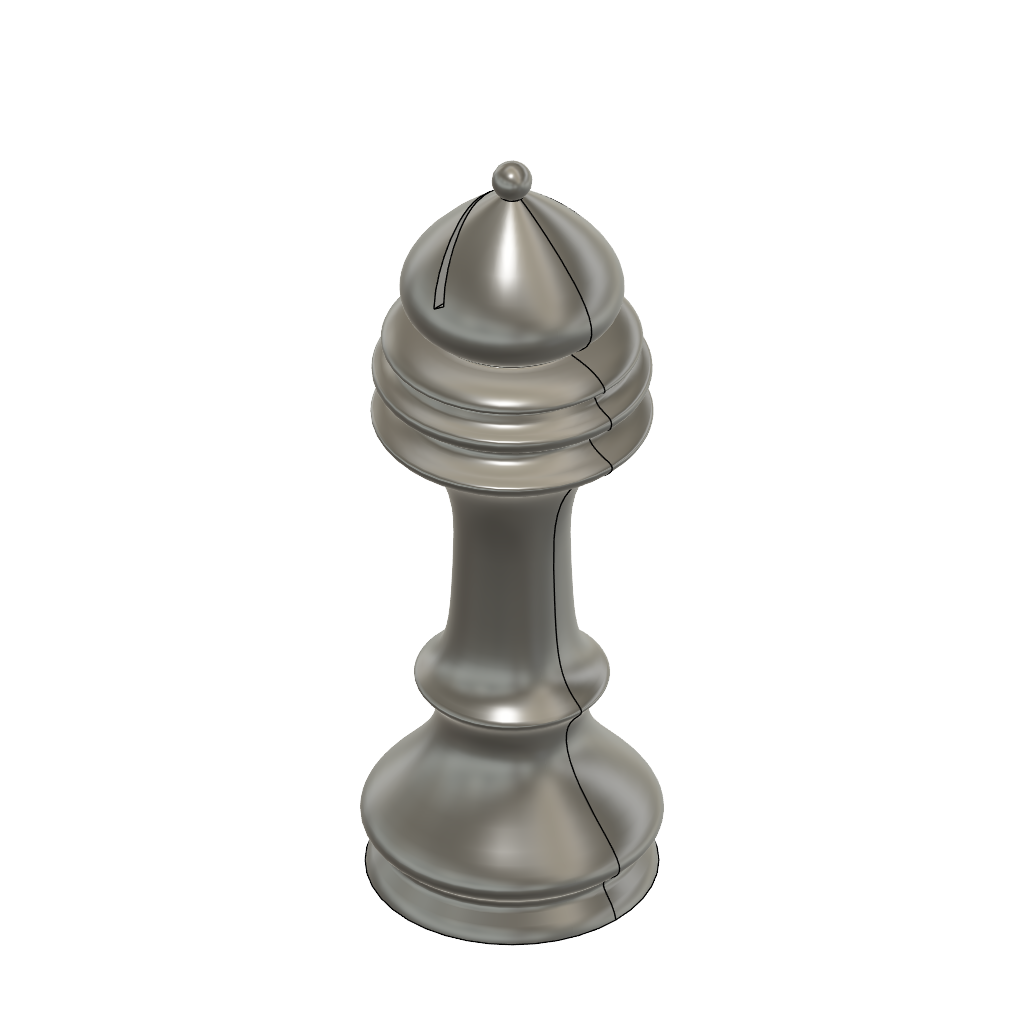
LED Chess board (Autodesk Fusion 360 archive; units mm, degrees)
design "bishop"
part number: 2026-10-17-16-16-12-997
Autodesk Fusion 360 part; units mm, degrees
sketch "Skizze1" plane through (0, 0, 0) normal (0, 0, 1) x (1, 0, 0)
  line L0 (0, 0) -> (12.5, 0)
  line L1 (0, 0) -> (0, 70) construction
  spline S0 degree 5 poles (12.5, 0) (12.4902, 0.0649) (12.4661, 0.1969) (12.416, 0.4015) (12.3214, 0.6876) (12.1519, 1.067) (11.9174, 1.467) (11.5844, 1.8858) (11.2355, 2.3113) (10.9882, 2.7293) (10.9544, 3.1282) (11.1766, 3.5057) (11.6006, 3.8716) (12.1184, 4.243) (12.5984, 4.6411) (12.9179, 5.0876) (13.0008, 5.6003) (12.8203, 6.1922) (12.3864, 6.8714) (11.7386, 7.6409) (10.9368, 8.4984) (10.0518, 9.4358) (9.1574, 10.4395) (8.3208, 11.4895) (7.5979, 12.5609) (7.0334, 13.6261) (6.6578, 14.6568) (6.4863, 15.6258) (6.5173, 16.5091) (6.7297, 17.2882) (7.0825, 17.9515) (7.5114, 18.4969) (7.9305, 18.9332) (8.2511, 19.2784) (8.4001, 19.5594) (8.3362, 19.8097) (8.0716, 20.0695) (7.6606, 20.3814) (7.1759, 20.7863) (6.6916, 21.3189) (6.259, 22.0026) (5.9036, 22.8494) (5.6322, 23.8609) (5.4376, 25.0301) (5.3036, 26.3418) (5.2098, 27.7748) (5.1375, 29.3022) (5.0738, 30.8934) (5.0183, 32.5147) (4.984, 34.1314) (5.0133, 35.7067) (5.1496, 37.21) (5.4161, 38.6195) (5.8237, 39.9193) (6.3685, 41.0987) (7.0338, 42.1508) (7.7885, 43.0704) (8.5911, 43.8548) (9.3825, 44.4973) (10.1036, 44.9969) (10.6552, 45.3322) (11.0078, 45.5269) (11.2638, 45.6847) (11.5257, 45.904) (11.832, 46.2343) (12.0716, 46.6199) (12.103, 46.9686) (11.8386, 47.2028) (11.3845, 47.335) (10.9172, 47.4277) (10.5924, 47.5551) (10.2606, 47.7112) (9.8506, 47.9071) (9.4622, 48.1865) (9.218, 48.5748) (9.2004, 49.0464) (9.4046, 49.5196) (9.7826, 49.9089) (10.2588, 50.1557) (10.7602, 50.2806) (11.2267, 50.3724) (11.6098, 50.528) (11.8746, 50.8134) (12.0012, 51.198) (11.9837, 51.5744) (11.8286, 51.8393) (11.5495, 51.9807) (11.1753, 52.0851) (10.7532, 52.249) (10.3855, 52.4876) (10.1754, 52.7133) (10.1691, 52.8431) (9.9754, 53.0668) (9.7447, 53.3785) (9.8496, 53.6537) (10.3106, 53.8551) (10.8687, 54.0261) (11.2023, 54.2348) (11.2197, 54.5308) (11.0003, 54.8982) (10.553, 55.2843) (9.9229, 55.626) (9.1678, 55.876) (8.3896, 56.0301) (7.7042, 56.1145) (7.2218, 56.174) (7.0225, 56.26) (7.1347, 56.4186) (7.5118, 56.6787) (8.0577, 57.0551) (8.6516, 57.5508) (9.1721, 58.1602) (9.5239, 58.8714) (9.6549, 59.669) (9.5456, 60.5347) (9.2037, 61.4482) (8.657, 62.3884) (7.9469, 63.3343) (7.1215, 64.2659) (6.2293, 65.1652) (5.3118, 66.0176) (4.4004, 66.8116) (3.5192, 67.5386) (2.6849, 68.1926) (1.9089, 68.7696) (1.198, 69.2672) (0.6841, 69.6008) (0.3299, 69.8146) (0.1076, 69.9409) (0, 70) knots 0 0 0 0 0 0 0.008 0.016 0.024 0.032 0.04 0.048 0.056 0.064 0.072 0.08 0.088 0.096 0.104 0.112 0.12 0.128 0.136 0.144 0.152 0.16 0.168 0.176 0.184 0.192 0.2 0.208 0.216 0.224 0.232 0.24 0.248 0.256 0.264 0.272 0.28 0.288 0.296 0.304 0.312 0.32 0.328 0.336 0.344 0.352 0.36 0.368 0.376 0.384 0.392 0.4 0.408 0.416 0.424 0.432 0.44 0.448 0.456 0.464 0.472 0.48 0.488 0.496 0.504 0.512 0.52 0.528 0.536 0.544 0.552 0.56 0.568 0.576 0.584 0.592 0.6 0.608 0.616 0.624 0.632 0.64 0.648 0.656 0.664 0.672 0.68 0.688 0.696 0.704 0.712 0.72 0.728 0.736 0.744 0.752 0.76 0.768 0.776 0.784 0.792 0.8 0.808 0.816 0.824 0.832 0.84 0.848 0.856 0.864 0.872 0.88 0.888 0.896 0.904 0.912 0.92 0.928 0.936 0.944 0.952 0.96 0.968 0.976 0.984 0.992 1 1 1 1 1 1
  line L2 (5.0217, 24.5299) -> (4.9783, 43.4701)
  line L3 (5.6926, 42.084) -> (14.4982, 47.8728)
  line L4 (16.7758, 45.0957) -> (4.5379, 49.9754)
  line L5 (12.3153, 48.6178) -> (8, 57)
  line L6 (0, 0) -> (0, 70)
  line L7 (8.6214, 50.7515) -> (13.6214, 57.7515)
  line L8 (0, 72.5) -> (0, 70)
  arc A0 (0, 69) -> (0, 72.5) centre (0, 70.75) ccw
  line L9 (16.0644, -5.4868) -> (8, 8)
  point P0 (11, 3)
  point P1 (12.6691, 4.7829)
  point P2 (9.7649, 9.7673)
  point P3 (7.0339, 17.8123)
  point P4 (8.3513, 19.616)
  point P5 (7, 21)
  point P6 (5, 34)
  point P7 (10.0954, 44.9784)
  point P8 (11.5172, 45.9131)
  point P9 (12, 47)
  point P10 (10.6569, 47.5356)
  point P11 (9.3545, 48.4077)
  point P12 (10, 50)
  point P13 (11.7197, 50.6781)
  point P14 (11.8806, 51.7076)
  point P15 (10.8459, 52.2279)
  point P16 (10.1576, 52.8089)
  point P17 (9.825, 53.4551)
  point P18 (11.1214, 54.2515)
  point P19 (9.9, 55.6)
  point P20 (7.1004, 56.2763)
  point P21 (9, 58)
  point P22 (6.688, 64.692)
  point P23 (12.0322, 1.2566)
  dimension "d1" = 12.5
  dimension "d2" = 70
  constraint coincident L0.start L1.start
  constraint horizontal L0
  constraint perpendicular L0 L1
  constraint midpoint P6 L2
  constraint midpoint P7 L3
  constraint midpoint P10 L4
  constraint midpoint P16 L5
  constraint coincident P17 L5
  constraint midpoint P18 L7
  constraint perpendicular L8 A0
  constraint coincident L1 A0.start
  constraint coincident P9 L4
  constraint coincident P8 L3
  constraint midpoint P23 L9
  measures "d1" distance of L0.start L0.end
  measures "d2" distance of L0.start L1.end
revolve "Drehen1" add sketch "Skizze1" angle 360 about axis through (0, 0, 0) along (0, 1, 0) contours L0 S0 L3 L4 L5 L6 A0 | S0 L6 A0 | S0 L8 A0 | S0 L5 | S0 L3 | S0 L5 | S0 L4 picked at (10.6146, 54.3176) picked at (11.265, 51.5423)
sketch "Skizze2" plane through (0, 0, 0) normal (0, 0, 1) x (1, 0, 0)
  line L0 (-3, 68) -> (0.4832, 62.22)
  line L1 (0.4832, 62.22) -> (-0.3733, 61.7039)
  line L2 (-0.3733, 61.7039) -> (-3.5, 67.8)
  line L3 (-3.5, 67.8) -> (-3, 68)
  constraint perpendicular L0 L1
extrude "Extrusion1" cut sketch "Skizze2" along normal mid plane 18
sketch "Skizze3" plane through (0, 0, 0) normal (0, -1, 0) x (1, 0, 0)
  circle A0 centre (0, 0) radius 12.5
  circle A1 centre (0, 0) radius 3.1
  dimension "d7" = 6.2
  constraint coincident A0.centre A1.centre
  measures "d7" diameter of A1
extrude "Extrusion2" cut sketch "Skizze3" against normal blind 2.2 from surface at -1 contours A1

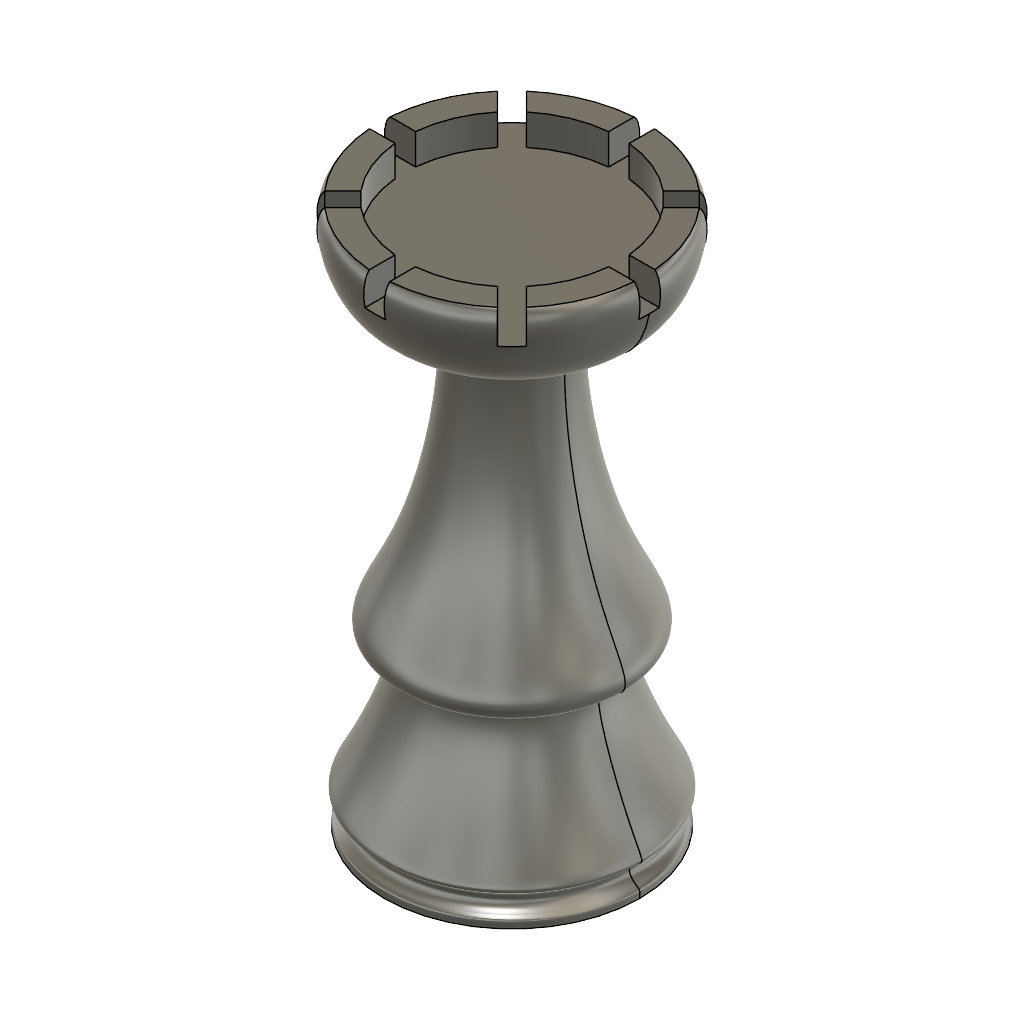
design "Rook"
part number: 2026-10-17-16-38-19-796
Autodesk Fusion 360 part; units mm, degrees
sketch "Skizze1" plane through (0, 0, 0) normal (0, 0, 1) x (1, 0, 0)
  line L0 (0, 0) -> (12.5, 0)
  line L1 (0, 0) -> (0, 55) construction
  spline S0 degree 5 poles (12.5, 0) (12.496, 0.0764) (12.4913, 0.2198) (12.4929, 0.4066) (12.5274, 0.6003) (12.469, 0.7684) (12.1651, 0.9447) (11.7687, 1.2269) (11.4658, 1.6185) (11.4353, 2.0612) (11.7248, 2.4765) (12.187, 2.8049) (12.5986, 3.0358) (12.7734, 3.2465) (12.658, 3.6182) (12.2775, 4.3343) (11.6926, 5.4701) (10.9789, 6.9837) (10.2231, 8.7583) (9.513, 10.6279) (8.9302, 12.4093) (8.5419, 13.9314) (8.3924, 15.0671) (8.4961, 15.7602) (8.8271, 16.0642) (9.3176, 16.1439) (9.8782, 16.1912) (10.4142, 16.3425) (10.8409, 16.6387) (11.0909, 17.0776) (11.1246, 17.6507) (10.9358, 18.3758) (10.5433, 19.2829) (9.9851, 20.4079) (9.3115, 21.7838) (8.5783, 23.4328) (7.8403, 25.3581) (7.1444, 27.5349) (6.5244, 29.9049) (6.0037, 32.3868) (5.597, 34.8833) (5.312, 37.2901) (5.1517, 39.5043) (5.1161, 41.4322) (5.2039, 42.9981) (5.4146, 44.1526) (5.7505, 44.8809) (6.2177, 45.2106) (6.8301, 45.2227) (7.6032, 45.0485) (8.5366, 44.8548) (9.6017, 44.8259) (10.7242, 45.1614) (11.7722, 46.0373) (12.6471, 47.3772) (13.2686, 48.9871) (13.5853, 50.6007) (13.5755, 51.9615) (13.2506, 52.8862) (12.6609, 53.3415) (11.8948, 53.5117) (10.9739, 53.5033) (9.8865, 53.4064) (8.5904, 53.2786) (7.0271, 53.1581) (5.131, 53.0654) (3.2996, 53.0204) (1.7287, 53.0037) (0.5913, 53) (0, 53) knots 0 0 0 0 0 0 0.01538462 0.03076923 0.04615385 0.06153846 0.07692308 0.09230769 0.10769231 0.12307692 0.13846154 0.15384615 0.16923077 0.18461538 0.2 0.21538462 0.23076923 0.24615385 0.26153846 0.27692308 0.29230769 0.30769231 0.32307692 0.33846154 0.35384615 0.36923077 0.38461538 0.4 0.41538462 0.43076923 0.44615385 0.46153846 0.47692308 0.49230769 0.50769231 0.52307692 0.53846154 0.55384615 0.56923077 0.58461538 0.6 0.61538462 0.63076923 0.64615385 0.66153846 0.67692308 0.69230769 0.70769231 0.72307692 0.73846154 0.75384615 0.76923077 0.78461538 0.8 0.81538462 0.83076923 0.84615385 0.86153846 0.87692308 0.89230769 0.90769231 0.92307692 0.93846154 0.95384615 0.96923077 0.98461538 1 1 1 1 1 1
  line L2 (12, 53) -> (-12, 53)
  line L3 (15, 51) -> (11, 55)
  line L4 (4.4639, 43.447) -> (15.5361, 46.553)
  line L5 (0, 53) -> (0, 0)
  line L6 (0, 53) -> (13, 53)
  line L7 (13.1, -3.6) -> (11.9, 4.8)
  point P0 (11.5, 2)
  point P1 (12.5, 3)
  point P2 (12.5, 3.9)
  point P3 (8.5, 15.5)
  point P4 (9.6872, 16.1845)
  point P5 (11, 17)
  point P6 (8, 25)
  point P7 (6, 45)
  point P8 (10, 45)
  point P9 (13, 53)
  point P10 (12.5, 0.6)
  point P11 (12.1, 1)
  dimension "d1" = 12.5
  dimension "d2" = 55
  constraint coincident L0.start L1.start
  constraint horizontal L0
  constraint perpendicular L0 L1
  constraint coincident L1 S0.end
  constraint midpoint S0.end L2
  constraint midpoint P9 L3
  constraint midpoint P8 L4
  constraint coincident P9 L6.end
  constraint midpoint P10 L7
  measures "d1" distance of L0.start L0.end
  measures "d2" distance of L0.start L1.end
revolve "Drehen1" add sketch "Skizze1" angle 360 about axis through (0, 53, 0) along (0, -1, 0) contours L0 S0 L2 L5 L6
sketch "Skizze2" plane through (0, 53, 0) normal (0, 1, 0) x (-1, 0, 0)
  circle A0 centre (0, 0) radius 13
  circle A1 centre (0, 0) radius 10.5
  line L0 (-10.5, -0.0167) -> (-13, -0.0207)
  line L1 (0.0012, 13) -> (0.001, 10.5)
  line L2 (13, -0.0208) -> (10.5, -0.0168)
  line L3 (-10.4539, 0.9833) -> (-13.0016, 0.9793)
  line L4 (-10.4507, -1.0166) -> (-13.6126, -1.0217)
  line L5 (-0.9988, 13.0001) -> (-0.9991, 10.4524)
  line L6 (1.0012, 13.7283) -> (1.0009, 10.4522)
  line L7 (13.0016, 0.9792) -> (10.4539, 0.9833)
  line L8 (14.002, -1.0224) -> (10.4507, -1.0167)
  line L9 (0, -13) -> (0, -10.5)
  line L10 (1, -13.5764) -> (1, -10.4523)
  line L11 (-1, -13) -> (-1, -10.4523)
  line L12 (1.0012, 13.7283) -> (-1, 13.7283)
  line L13 (-13.6126, 0.9872) -> (-13.6126, -1.0217)
  line L14 (1, -13.5764) -> (-0.9966, -13.5764)
  line L15 (14.002, 0.9666) -> (14.002, -1.0224)
  line L16 (-1, -13) -> (-0.9966, -13.5764)
  line L17 (-13.0016, 0.9793) -> (-13.6126, 0.9872)
  line L18 (-1, 13.7283) -> (-0.9988, 13.0001)
  line L19 (13.0016, 0.9792) -> (14.002, 0.9666)
  line L20 (0, 0) -> (7.4246, -7.4246)
  line L21 (0, 0) -> (10.5, 0) construction
  line L22 (7.4246, -7.4246) -> (9.1924, -9.1924)
  line L23 (8.458, -9.8723) -> (6.6838, -8.098)
  line L24 (9.8723, -8.458) -> (8.098, -6.6838)
  line L25 (0, 0) -> (-7.4246, -7.4246)
  line L26 (0, 0) -> (10.5, 0) construction
  line L27 (0, 0) -> (-7.4246, 7.4246)
  line L28 (0, 0) -> (7.4246, 7.4246)
  line L29 (-7.4246, -7.4246) -> (-9.1924, -9.1924)
  line L30 (-8.098, -6.6838) -> (-9.8723, -8.458)
  line L31 (-6.6838, -8.098) -> (-8.458, -9.8723)
  line L32 (-7.4246, 7.4246) -> (-9.1924, 9.1924)
  line L33 (-8.098, 6.6838) -> (-9.8723, 8.458)
  line L34 (-6.6838, 8.098) -> (-8.458, 9.8723)
  line L35 (7.4246, 7.4246) -> (9.1924, 9.1924)
  line L36 (8.098, 6.6838) -> (9.8723, 8.458)
  line L37 (7.4246, 7.4246) -> (9.1924, 9.1924)
  line L38 (6.6838, 8.098) -> (8.458, 9.8723)
  line L39 (-9.8723, 8.458) -> (-10.5603, 9.1461)
  line L40 (-10.5603, 9.1461) -> (-9.1217, 10.5846)
  line L41 (-9.1217, 10.5846) -> (-8.458, 9.8723)
  line L42 (8.458, 9.8723) -> (9.109, 10.4786)
  line L43 (9.109, 10.4786) -> (10.5003, 8.9851)
  line L44 (10.5003, 8.9851) -> (9.8723, 8.458)
  line L45 (-9.8723, -8.458) -> (-10.7536, -9.3394)
  line L46 (-10.7536, -9.3394) -> (-9.344, -10.749)
  line L47 (-9.344, -10.749) -> (-8.458, -9.8723)
  line L48 (8.458, -9.8723) -> (9.1266, -10.5408)
  line L49 (9.1266, -10.5408) -> (10.5416, -9.1258)
  line L50 (10.5416, -9.1258) -> (9.8723, -8.458)
  dimension "d4" = 21
  dimension "d7" = 1
  dimension "d8" = -1
  dimension "d9" = 1
  dimension "d10" = -1
  dimension "d11" = 1
  dimension "d12" = -1
  dimension "d15" = 1
  dimension "d16" = -1
  dimension "d17" = 45
  dimension "d18" = 1
  dimension "d19" = 1
  dimension "d20" = 135
  dimension "d21" = 90
  dimension "d22" = 90
  dimension "d23" = 1
  dimension "d24" = 1
  dimension "d25" = 1
  dimension "d26" = 1
  dimension "d27" = 1
  dimension "d29" = 1
  constraint coincident A0.centre A1.centre
  constraint coincident A1 L0.start
  constraint coincident A0 L0.end
  constraint perpendicular A0 L0
  constraint coincident A0 L1.start
  constraint coincident A1 L1.end
  constraint perpendicular A1 L1
  constraint coincident A0 L2.start
  constraint coincident A1 L2.end
  constraint perpendicular A0 L2
  constraint coincident A1 L4.start
  constraint coincident A1 L8.end
  constraint coincident A1 L7.end
  constraint coincident A1 L6.end
  constraint coincident A1 L5.end
  constraint coincident A1 L3.start
  constraint coincident A0 L9.start
  constraint coincident A1 L9.end
  constraint perpendicular A1 L9
  constraint coincident A1 L11.end
  constraint vertical L11
  constraint coincident A1 L10.end
  constraint horizontal L12
  constraint vertical L13
  constraint horizontal L14
  constraint vertical L15
  constraint horizontal L21
  constraint coincident A1 L20.end
  constraint coincident A0 L22.end
  constraint perpendicular A0 L22
  constraint coincident A0 L23.start
  constraint coincident A1 L23.end
  constraint parallel L22 L23
  constraint coincident A0 L24.start
  constraint coincident A1 L24.end
  constraint parallel L22 L24
  constraint horizontal L26
  constraint coincident A1 L25.end
  constraint coincident A1 L27.end
  constraint coincident A1 L28.end
  constraint coincident A0 L29.end
  constraint perpendicular A0 L29
  constraint coincident A1 L30.start
  constraint coincident A0 L30.end
  constraint parallel L29 L30
  constraint coincident A1 L31.start
  constraint coincident A0 L31.end
  constraint parallel L29 L31
  constraint coincident A0 L32.end
  constraint perpendicular A0 L32
  constraint coincident A1 L33.start
  constraint coincident A0 L33.end
  constraint parallel L32 L33
  constraint coincident A1 L34.start
  constraint coincident A0 L34.end
  constraint parallel L32 L34
  constraint coincident A0 L35.end
  constraint perpendicular A0 L35
  constraint coincident A1 L36.start
  constraint coincident A0 L36.end
  constraint parallel L35 L36
  constraint coincident A1 L38.start
  constraint coincident A0 L38.end
  constraint parallel L37 L38
  constraint parallel L33 L39
  constraint perpendicular L39 L40
  constraint perpendicular L41 L42
  constraint perpendicular L42 L43
  constraint parallel L30 L45
  constraint perpendicular L45 L46
  constraint perpendicular L48 L49
  measures "d4" diameter of A1
  measures "d17" angle of L20 L21
  measures "d18" distance of L22 L23
  measures "d19" distance of L22 L24
  measures "d20" angle of L25 L26
  measures "d21" angle of L25 L27
  measures "d22" angle of L27 L28
  measures "d23" distance of L29 L31
  measures "d24" distance of L29 L30
  measures "d25" distance of L32 L33
  measures "d26" distance of L32 L34
  measures "d27" distance of L35 L36
  measures "d29" distance of L37 L38
extrude "Extrusion1" cut sketch "Skizze2" against normal blind 3 contours A0 A1 L35 L36 L37 | A0 L42 L43 L44 | A0 A1 L35 L37 L38 | A0 L7 L8 L15 L19 | A0 A1 L2 L7 | A1 L20 L28 | A1 L27 L28 | A0 A1 L1 L6 | A0 L5 L6 L12 L18 | A1 L20 L25 | A1 L25 L27 | A0 A1 L2 L8 | A0 A1 L1 L5 | A0 A1 L22 L23 | A0 A1 L22 L24 | A0 A1 L29 L30 | A0 A1 L29 L31 | A0 A1 L32 L34 | A0 A1 L32 L33 | A0 L48 L49 L50 | A0 L45 L46 L47 | A0 L39 L40 L41 | A0 A1 L9 L10 | A0 A1 L0 L4 | A0 A1 L9 L11 | A0 A1 L0 L3 | A0 L10 L11 L14 L16 | A0 L3 L4 L13 L17
sketch "Skizze3" plane through (0, 0, 0) normal (0, -1, 0) x (1, 0, 0)
  circle A0 centre (0, 0) radius 12.5
  circle A1 centre (0, 0) radius 3.1
  dimension "d30" = 6.2
  constraint coincident A0.centre A1.centre
  measures "d30" diameter of A1
extrude "Extrusion2" cut sketch "Skizze3" against normal blind 2.2 from surface at -1 contours A1
equation "d8 = -d7"
equation "d10 = -d9"
equation "d12 = -d11"
equation "d16 = -d15"

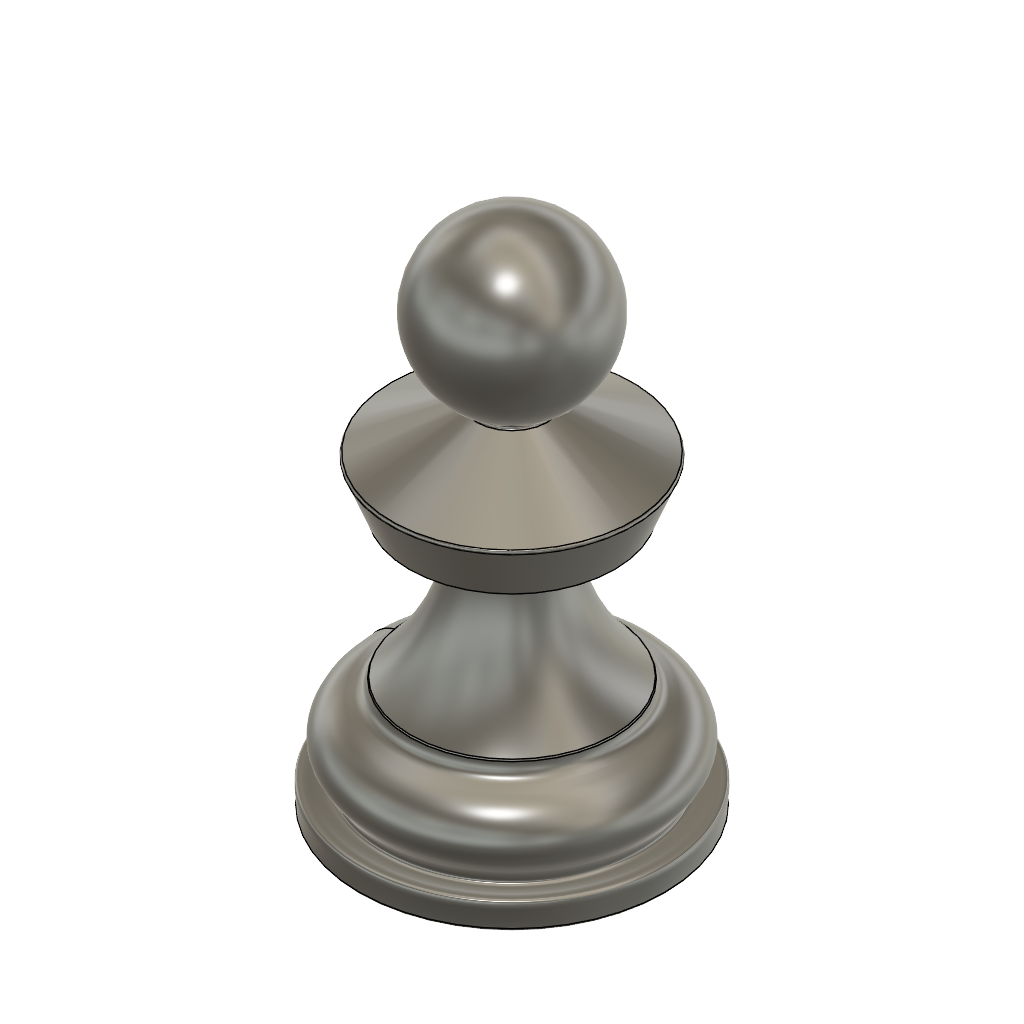
design "pawn"
part number: 2026-10-17-15-36-41-992
Autodesk Fusion 360 part; units mm, degrees
sketch "Skizze2" plane through (0, 0, 0) normal (0, 0, 1) x (1, 0, 0)
  line L0 (0, 0) -> (0, 50) construction
  arc A0 (-9.9334, 11.0573) -> (-4.4469, 24.7483) centre (-24.6204, 24.8877) ccw
  spline S0 degree 5 poles (-14.9873, 0.2585) (-14.9832, 0.3802) (-14.9787, 0.619) (-14.9837, 0.9638) (-15.0127, 1.3971) (-15.0755, 1.8936) (-15.1061, 2.3136) (-15.0253, 2.6149) (-14.6044, 2.6522) (-13.8818, 2.4756) (-13.1074, 2.2825) (-12.5495, 2.2659) (-12.4118, 2.5566) (-12.5812, 3.0054) (-12.9164, 3.4943) (-13.3205, 3.9863) (-13.7088, 4.4747) (-14.0216, 4.9773) (-14.2186, 5.5118) (-14.2805, 6.0782) (-14.2045, 6.6625) (-14.0007, 7.2419) (-13.6878, 7.7895) (-13.2895, 8.2787) (-12.8305, 8.6883) (-12.3349, 9.0068) (-11.8276, 9.2356) (-11.3347, 9.3957) (-10.883, 9.5246) (-10.5053, 9.6993) (-10.2227, 9.9707) (-10.0803, 10.2801) (-10.022, 10.566) (-10.0046, 10.7802) (-10.0013, 10.8932) knots 0 0 0 0 0 0 0.033333 0.066667 0.1 0.133333 0.166667 0.2 0.233333 0.266667 0.3 0.333333 0.366667 0.4 0.433333 0.466667 0.5 0.533333 0.566667 0.6 0.633333 0.666667 0.7 0.733333 0.766667 0.8 0.833333 0.866667 0.9 0.933333 0.966667 1 1 1 1 1 1
  line L1 (-15.5, 1.9) -> (-14.5, 3.1)
  line L2 (-12.7, 1.8) -> (-12.3, 3.2)
  line L3 (-12.2831, 9.0533) -> (-9.7169, 9.9467)
  line L4 (-10.0629, 25.1572) -> (-11.9152, 29.788)
  line L5 (-11.7965, 30.1036) -> (-3.4683, 34.3453)
  line L6 (0, 0) -> (-14.7375, 0)
  arc A1 (0, 50) -> (-3.4732, 34.7933) centre (0, 42) ccw
  line L7 (0, 0) -> (0, 50)
  arc A2 (-3.4683, 34.3453) -> (-3.4732, 34.7933) centre (-3.5817, 34.5681) ccw
  arc A3 (-11.7965, 30.1036) -> (-11.9152, 29.788) centre (-11.6831, 29.8809) ccw
  arc A4 (-10.0629, 25.1572) -> (-9.8307, 25) centre (-9.8307, 25.25) ccw
  arc A5 (-9.9334, 11.0573) -> (-10.0013, 10.8932) centre (-9.7514, 10.8859) ccw
  arc A6 (-14.9873, 0.2585) -> (-14.7375, 0) centre (-14.7375, 0.25) ccw
  line L8 (-4.6969, 25) -> (-9.8307, 25)
  arc A7 (-4.4469, 24.7483) -> (-4.6969, 25) centre (-4.6969, 24.75) ccw
  point P0 (-15, 2.5)
  point P1 (-12.5, 2.5)
  point P2 (-14, 5)
  point P3 (-13.5, 8)
  point P4 (-11, 9.5)
  dimension "d6" = 50
  dimension "d8" = 0.25
  dimension "d9" = 0.25
  constraint coincident L0.start L6.start
  constraint vertical L0
  constraint midpoint P0 L1
  constraint midpoint P1 L2
  constraint midpoint P4 L3
  constraint perpendicular L0 L6
  constraint perpendicular A1 L7
  constraint tangent A1 A2
  constraint tangent L5 A2
  constraint tangent L5 A3
  constraint tangent L4 A3
  constraint equal A2 A3
  constraint tangent L4 A4
  constraint equal A2 A4
  constraint tangent A0 A5
  constraint tangent S0 A5
  constraint equal A2 A5
  constraint tangent S0 A6
  constraint tangent L6 A6
  constraint equal A2 A6
  constraint tangent A4 L8
  constraint tangent L8 A7
  constraint tangent A0 A7
  measures "d6" distance of L0.start L0.end
  measures "d8" radius of A2
  measures "d9" radius of A7
revolve "Drehen1" add sketch "Skizze2" angle 360 about axis through (0, 0, 0) along (0, 1, 0)
sketch "Skizze3" plane through (0, 0, 0) normal (0, -1, 0) x (1, 0, 0)
  circle A0 centre (0, 0) radius 14.7375
  circle A1 centre (0, 0) radius 3.1
  dimension "d10" = 6.2
  constraint coincident A0.centre A1.centre
  measures "d10" diameter of A1
extrude "Extrusion2" cut sketch "Skizze3" against normal blind 2.2 from surface at -1 contours A1
